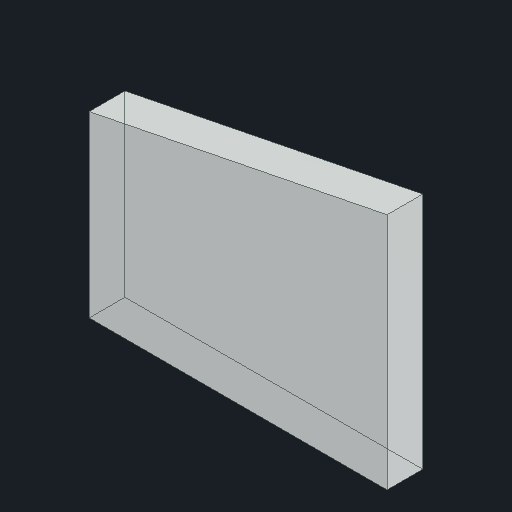
# Autodesk Inventor part: 7_6_4_feu_avant
Saved by Autodesk Inventor 2026 (Build 300175000, 175)
## iProperties
Created: 2025-06-22
Part Number: 7_6_4_feu_avant
Material: Glass
Document SubType Name: Modeling
Designer: remg9
Density: 2.18 g/cm^3
Appearance: Clear
Author: remg9
Autodesk Inventor part; units mm, degrees
ref_plane "YZ Plane" through (0, 0, 0) normal (1, 0, 0) x (0, 1, 0)
ref_plane "XZ Plane" through (0, 0, 0) normal (0, 1, 0) x (-1, 0, 0)
ref_plane "XY Plane" through (0, 0, 0) normal (0, 0, 1) x (1, 0, 0)
sketch "Sketch1" plane through (0, 0, 0) normal (0, 0, 1) x (1, 0, 0)
  line L0 (0, 0) -> (0, 15)
  line L1 (0, 15) -> (25, 20)
  line L2 (25, 20) -> (25, 0)
  line L3 (25, 0) -> (0, 0)
  dimension "d0" = 15
  dimension "d1" = 20
  dimension "d2" = 25
  constraints: 8 end point, 1 parallel, 1 perpendicular, 1 vertical
  measures "d0" distance of L0.start L0.end
  measures "d1" distance of L1.end L2.end
  measures "d2" distance of L2.end L0.start
extrude "Extrusion1" add sketch "Sketch1" along normal blind 3
body "Solid1"
